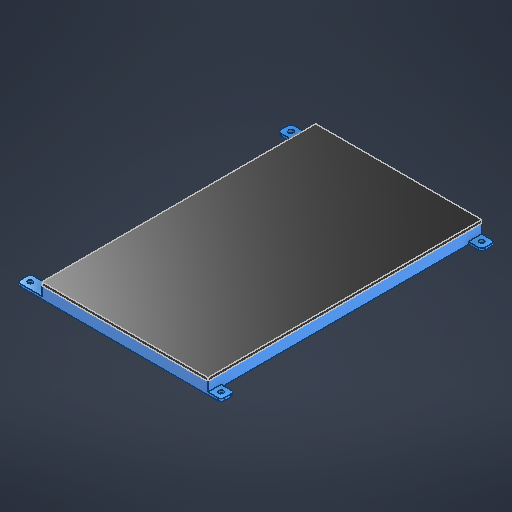
# Autodesk Inventor part: 7inch diplay
Saved by Autodesk Inventor 2027.1 (Build 311270010, 270A)
## iProperties
Created: 2026-07-10
Part Number: 7inch diplay
Material: 일반
Document SubType Name: Modeling
Designer: work
Density: 1 g/cm^3
Appearance: 기본값
Author: work
Autodesk Inventor part; units mm, degrees
ref_plane "YZ Plane" through (0, 0, 0) normal (1, 0, 0) x (0, 1, 0)
ref_plane "XZ Plane" through (0, 0, 0) normal (0, 1, 0) x (-1, 0, 0)
sketch "스케치1" plane through (0, 0, 0) normal (0, 1, 0) x (-1, 0, 0)
  line L0 (-50, 82.5) -> (50, 82.5)
  line L1 (50, 82.5) -> (50, -82.5)
  line L2 (50, -82.5) -> (-50, -82.5)
  line L3 (-50, -82.5) -> (-50, 82.5)
  line L4 (-50, 82.5) -> (50, -82.5) construction
  line L5 (50, 82.5) -> (-50, -82.5) construction
  point P0 (0, 0)
  dimension "d0" = 100
  dimension "d1" = 165
  constraints: 12 end point, 2 midpoint, 2 parallel, 1 horizontal, 1 perpendicular
  measures "d0" distance of L1.end L2.end
  measures "d1" distance of L0.end L1.end
extrude "돌출1" add sketch "스케치1" along normal blind 9
sketch "스케치2" plane through (0, 0, 0) normal (0, -1, 0) x (1, 0, 0)
  line L0 (58, 82.5) -> (-65, 82.5)
  line L1 (-65, 82.5) -> (-65, -82.5)
  line L2 (-65, -82.5) -> (58, -82.5)
  line L3 (58, -82.5) -> (58, 82.5)
  line L4 (50, 82.5) -> (50, -82.5) projected
  line L5 (-50, -82.5) -> (-50, 82.5) projected
  line L6 (-65, 74.5) -> (-56, 74.5)
  line L7 (-56, 74.5) -> (-56, -74.5)
  line L8 (-56, -74.5) -> (-65, -74.5)
  line L9 (-65, -74.5) -> (-65, 74.5)
  line L10 (58, 74.5) -> (50, 74.5)
  line L11 (50, 74.5) -> (50, -74.5)
  line L12 (50, -74.5) -> (58, -74.5)
  line L13 (58, -74.5) -> (58, 74.5)
  point P0 (0, 0)
  point P1 (-65, 0)
  point P2 (58, 0)
  point P3 (50, 0)
  dimension "d4" = 8
  dimension "d5" = 15
  dimension "d6" = 6
  dimension "d7" = 8
  dimension "d8" = 8
  constraints: 24 end point, 6 midpoint, 6 parallel, 3 horizontal, 3 perpendicular, 2 point on line
  measures "d4" distance between parallel lines of L4 L3
  measures "d5" distance between parallel lines of L1 L5
  measures "d6" distance between parallel lines of L5 L7
  measures "d7" distance between parallel lines of L2 L8
  measures "d8" distance between parallel lines of L0 L10
extrude "돌출2" add sketch "스케치2" against normal blind 1.5 contours L3 L10 L4 L0 | L5 L2 L1 L8 L7 L6 L0 | L3 L2 L4 L12
fillet "모깎기1" radius 2 8 edges at (58, 0.75, -74.5) (58, 0.75, -82.5) (58, 0.75, 82.5) (58, 0.75, 74.5) (-65, 0.75, 82.5) (-65, 0.75, 74.5) (-65, 0.75, -82.5) (-65, 0.75, -74.5)
sketch "스케치3" plane through (0, 1.5, 0) normal (0, 1, 0) x (1, 0, 0)
  arc A0 (-65, 76.5) -> (-63, 74.5) centre (-63, 76.5) ccw projected
  line L0 (-63, 74.5) -> (-56, 74.5) projected
  line L1 (-56, 74.5) -> (-56, -74.5) projected
  line L2 (-56, -74.5) -> (-63, -74.5) projected
  arc A1 (-63, -74.5) -> (-65, -76.5) centre (-63, -76.5) ccw projected
  line L3 (-65, -76.5) -> (-65, -80.5) projected
  arc A2 (-65, -80.5) -> (-63, -82.5) centre (-63, -80.5) ccw projected
  line L4 (-63, -82.5) -> (-50, -82.5) projected
  line L5 (-50, 82.5) -> (-50, -82.5) projected
  line L6 (-50, 82.5) -> (-63, 82.5) projected
  arc A3 (-63, 82.5) -> (-65, 80.5) centre (-63, 80.5) ccw projected
  line L7 (-65, 80.5) -> (-65, 76.5) projected
  arc A4 (58, 80.5) -> (56, 82.5) centre (56, 80.5) ccw projected
  line L8 (56, 82.5) -> (50, 82.5) projected
  line L9 (50, 74.5) -> (50, 82.5) projected
  line L10 (50, 74.5) -> (56, 74.5) projected
  arc A5 (56, 74.5) -> (58, 76.5) centre (56, 76.5) ccw projected
  line L11 (58, 76.5) -> (58, 80.5) projected
  arc A6 (58, -76.5) -> (56, -74.5) centre (56, -76.5) ccw projected
  line L12 (56, -74.5) -> (50, -74.5) projected
  line L13 (50, -82.5) -> (50, -74.5) projected
  line L14 (50, -82.5) -> (56, -82.5) projected
  arc A7 (56, -82.5) -> (58, -80.5) centre (56, -80.5) ccw projected
  line L15 (58, -80.5) -> (58, -76.5) projected
  point P0 (0, 0)
  point P1 (-61, -78.5)
  point P2 (-61, 78.5)
  point P3 (54, 78.5)
  point P4 (54, -78.5)
  dimension "d12" = 4
  dimension "d13" = 4
  dimension "d14" = 4
  dimension "d15" = 4
  dimension "d16" = 4
  dimension "d17" = 4
  dimension "d18" = 4
  dimension "d19" = 4
  measures "d12" distance from line of L2 point (-61, -78.5)
  measures "d13" distance from line of L3 point (-61, -78.5)
  measures "d14" distance from line of L15 point (54, -78.5)
  measures "d15" distance from line of L14 point (54, -78.5)
  measures "d16" distance from line of L11 point (54, 78.5)
  measures "d17" distance from line of L8 point (54, 78.5)
  measures "d18" distance from line of L6 point (-61, 78.5)
  measures "d19" distance from line of L7 point (-61, 78.5)
hole "구멍1" at (-61, 1.5, 78.5) at (-61, 1.5, -78.5) at (54, 1.5, -78.5) at (54, 1.5, 78.5) direction (0, -1, 0) diameter 3 end through all
ref_plane "작업 평면1" through (0, 7, 0) normal (0, 1, 0) x (1, 0, 0)
split body "분할1" result two bodies by plane through (0, 7, 0) normal (0, 1, 0) first body at (16.6667, 8.5, 27.5)
